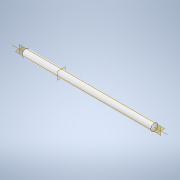
# Autodesk Inventor part: 1.3_3_Shaft_A
Saved by Autodesk Inventor 2021 (Build 250183000, 183)
## iProperties
Created: 2025-11-13
Part Number: 1.3_3_Shaft_A
Material: Aluminum 6061
Document SubType Name: Modeling
Designer: Admin
Density: 2.7 g/cm^3
Appearance: Aluminum - Flat
Author: Admin
Autodesk Inventor part; units mm, degrees
sketch "Sketch1" plane through (0, 0, 0) normal (0, 1, 0) x (-1, 0, 0)
  line L0 (50, 0) -> (-130, 0)
  line L1 (-130, 0) -> (-130, -5)
  line L2 (-130, -5) -> (50, -5)
  line L3 (50, -5) -> (50, 0)
  line L4 (86, 0) -> (-166, 0) projected
  line L5 (0, -6) -> (0, 1) projected
  point P0 (0, 0)
  dimension "d0" = 180
  dimension "d1" = 5
  dimension "d2" = 50
  constraints: 8 end point, 2 perpendicular, 1 collinear, 1 horizontal, 1 parallel
  measures "d0" distance of L1.end L2.end
  measures "d1" distance of L2.end L0.start
  measures "d2" distance between parallel lines of L5 L3
revolve "Revolution1" add sketch "Sketch1" angle 360 about axis through (-10, 0, 0) along (1, 0, 0)
body "Solid1"
